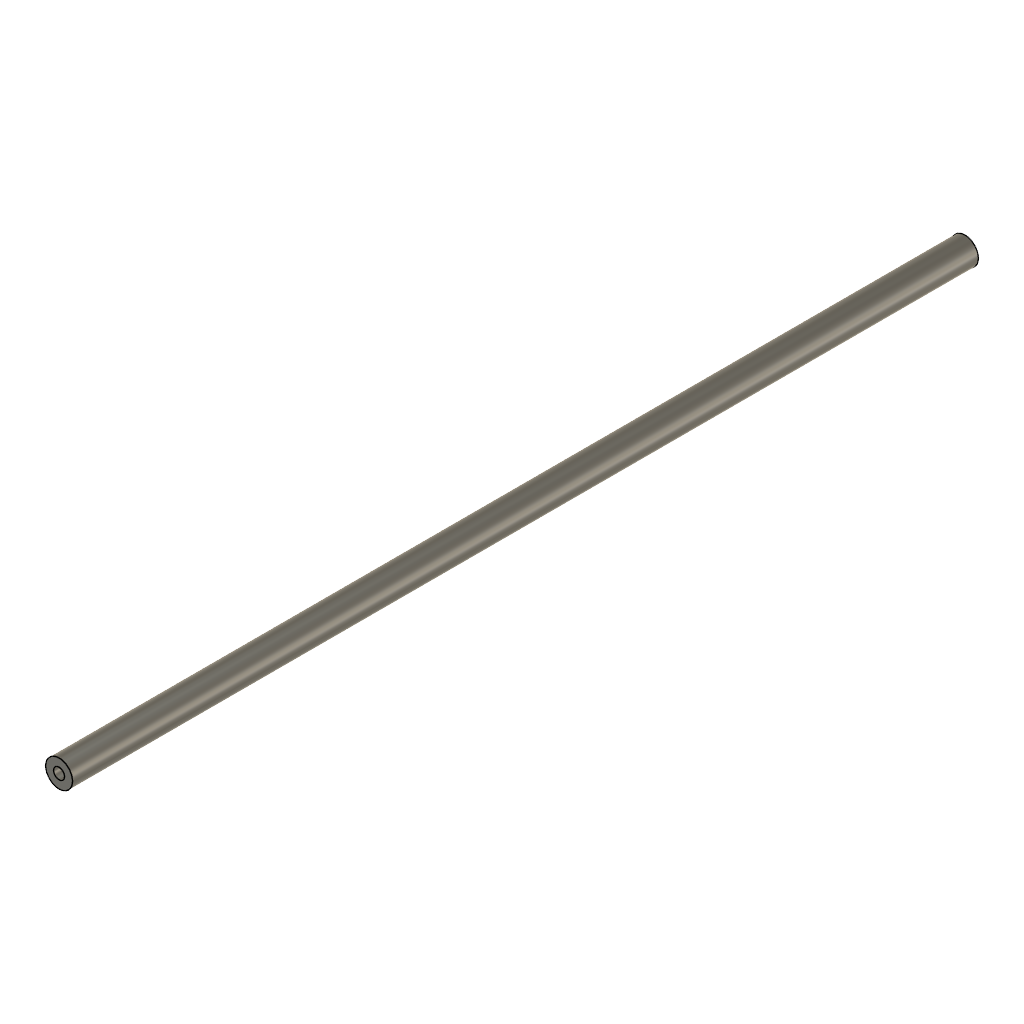
sliding rod (Autodesk Fusion 360 design; units mm, degrees)
part number: 2026-11-08-18-01-10-733
Autodesk Fusion 360 part; units mm, degrees
sketch "Sketch1" plane through (0, 92.5, 0) normal (0, -1, 0) x (1, 0, 0)
  line L0 (144, 3.5) -> (130.5, 3.5)
  line L1 (130.5, 3.5) -> (130.5, -12)
  line L2 (130.5, -12) -> (144, -12)
  line L3 (144, -12) -> (144, 3.5)
  circle A0 centre (137.25, -4.25) radius 4
  circle A1 centre (137.25, -4.25) radius 2
  dimension "d1" = 8
  dimension "d2" = 4
  constraint concentric A0 A1
  measures "d1" diameter of A0
  measures "d2" diameter of A1
sketch "Sketch2" plane through (0, 95, 0) normal (0, 1, 0) x (-1, 0, 0)
  line L0 (-130.5, -12) -> (-130.5, 3.5)
  line L1 (-130.5, 3.5) -> (-144, 3.5)
  line L2 (-144, 3.5) -> (-144, -12)
  line L3 (-144, -12) -> (-130.5, -12)
  circle A0 centre (-137.25, -4.25) radius 1
  circle A1 centre (-137.25, -4.25) radius 1
  dimension "d3" = 2
  constraint concentric A0 A1
  measures "d3" diameter of A0
sketch "Sketch3" plane through (0, -42.5, 0) normal (0, -1, 0) x (1, 0, 0)
  line L0 (144, 3.5) -> (130.5, 3.5)
  line L1 (130.5, 3.5) -> (130.5, -12)
  line L2 (130.5, -12) -> (144, -12)
  line L3 (144, -12) -> (144, 3.5)
  circle A0 centre (137.25, -4.25) radius 2
  circle A1 centre (137.25, -4.25) radius 2
  circle A2 centre (137.25, -4.25) radius 1
  dimension "d4" = 4
  dimension "d5" = 2
  constraint concentric A0 A1
  constraint concentric A0 A2
  measures "d4" diameter of A0
  measures "d5" diameter of A2
extrude "Extrude1" add sketch "Sketch1" along normal blind 133.5 contours A1
extrude "Extrude2" cut sketch "Sketch3" against normal blind 6 contours A2
extrude "Extrude3" cut sketch "Sketch2" against normal blind 6 contours A0 A1
thread "Thread1" "ISO Metric profile 2.0 M2x0.4 M2x0.4 6H" major diameter 2.074 minor diameter 1.623 pitch 0.4 angle 60 resizes the face on face at (138.1715, 90.1667, -4.6384)
thread "Thread2" "ISO Metric profile 2.0 M2x0.4 M2x0.4 6H" major diameter 2.074 minor diameter 1.623 pitch 0.4 angle 60 resizes the face on face at (136.3103, -38, -4.592)
